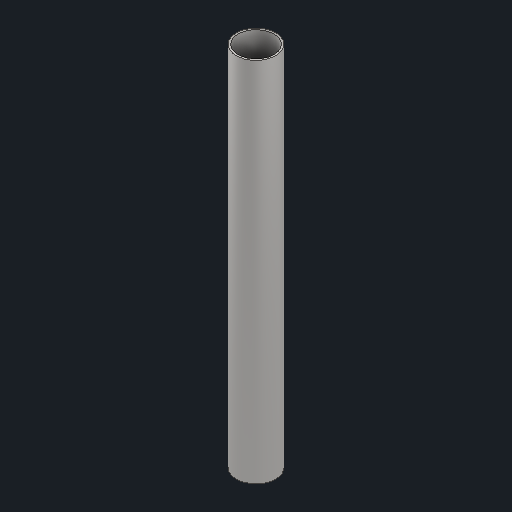
# Autodesk Inventor part: tripod_leg_upper
Saved by Autodesk Inventor 2027.1 (Build 311270010, 270A)
## iProperties
Created: 2026-11-04
Part Number: tripod_leg_upper
Material: Generic
Description: 2 in stainless upper leg (full length, replaces the cut-short stub)
Document SubType Name: Modeling
Designer: Claude (from photos)
Density: 1 g/cm^3
Appearance: Stainless - Satin
Author: alexg
Autodesk Inventor part; units mm, degrees
ref_plane "YZ Plane" through (0, 0, 0) normal (1, 0, 0) x (0, 1, 0)
ref_plane "XY Plane" through (0, 0, 0) normal (0, 0, 1) x (1, 0, 0)
ref_plane "Work Plane1" through (0, -130, 0) normal (0, 1, 0) x (-1, 0, 0)
sketch "Upper leg 2in sketch" plane through (0, -130, 0) normal (0, 1, 0) x (-1, 0, 0)
  circle A0 centre (0, 0) radius 25.4
  circle A1 centre (0, 0) radius 23
  constraints: 2 centre point
extrude "Upper leg 2in" add sketch "Upper leg 2in sketch" against normal blind 470
body "Solid1"
